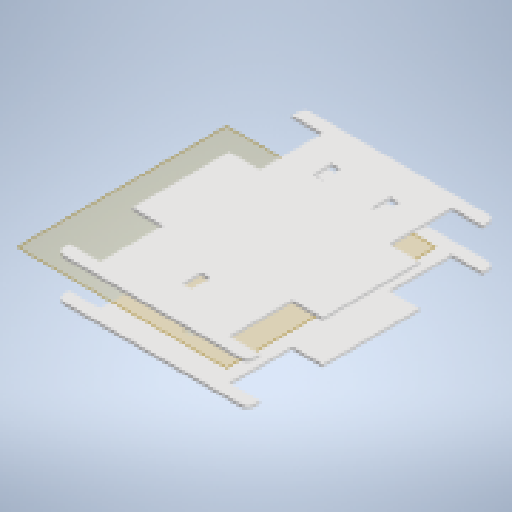
# Autodesk Inventor part: base
Saved by Autodesk Inventor 2025.2 (Build 292293000, 293)
## iProperties
Created: 2026-05-19
Part Number: base
Material: Generic
Document SubType Name: Modeling
Designer: joaoc
Density: 1 g/cm^3
Appearance: Default
Author: joaoc
Autodesk Inventor part; units mm, degrees
ref_plane "YZ Plane" through (0, 0, 0) normal (1, 0, 0) x (0, 1, 0)
ref_plane "XZ Plane" through (0, 0, 0) normal (0, 1, 0) x (-1, 0, 0)
ref_plane "XY Plane" through (0, 0, 0) normal (0, 0, 1) x (1, 0, 0)
sketch "Sketch1" plane through (0, 0, 0) normal (0, 1, 0) x (-1, 0, 0)
  line L0 (-400, 0) -> (-400, 13.2)
  arc A0 (-386.8, 26.4) -> (-400, 13.2) centre (-386.8, 13.2) ccw
  line L1 (-386.8, 26.4) -> (-13.2, 26.4)
  arc A1 (0, 13.2) -> (-13.2, 26.4) centre (-13.2, 13.2) ccw
  line L2 (0, 13.2) -> (0, 0)
  line L3 (-400, -335.4) -> (-335.4, -335.4)
  line L4 (-335.4, -335.4) -> (-335.4, -467.2)
  line L5 (-335.4, -467.2) -> (-400, -467.2)
  line L6 (-400, -131.8) -> (-335.4, -131.8)
  line L7 (-335.4, -131.8) -> (-335.4, 0)
  line L8 (-335.4, 0) -> (-400, 0)
  line L9 (0, -335.4) -> (-64.6, -335.4)
  line L10 (-64.6, -335.4) -> (-64.6, -467.2)
  line L11 (-64.6, -467.2) -> (0, -467.2)
  line L12 (0, -131.8) -> (-64.6, -131.8)
  line L13 (-64.6, -131.8) -> (-64.6, 0)
  line L14 (-64.6, 0) -> (0, 0)
  line L15 (-400, -335.4) -> (-400, -131.8)
  line L16 (0, -467.2) -> (0, -480.4)
  arc A2 (-13.2, -493.6) -> (0, -480.4) centre (-13.2, -480.4) ccw
  line L17 (-13.2, -493.6) -> (-386.8, -493.6)
  arc A3 (-400, -480.4) -> (-386.8, -493.6) centre (-386.8, -480.4) ccw
  line L18 (-400, -480.4) -> (-400, -467.2)
  line L19 (0, -131.8) -> (0, -335.4)
  line L20 (-210, -45.9) -> (-190, -45.9)
  line L21 (-190, -45.9) -> (-190, -85.9)
  line L22 (-190, -85.9) -> (-210, -85.9)
  line L23 (-210, -85.9) -> (-210, -45.9)
  line L24 (-271.3, -381.3) -> (-251.3, -381.3)
  line L25 (-251.3, -381.3) -> (-251.3, -421.3)
  line L26 (-251.3, -421.3) -> (-271.3, -421.3)
  line L27 (-271.3, -421.3) -> (-271.3, -381.3)
  line L28 (-148.7, -381.3) -> (-128.7, -381.3)
  line L29 (-128.7, -381.3) -> (-128.7, -421.3)
  line L30 (-128.7, -421.3) -> (-148.7, -421.3)
  line L31 (-148.7, -421.3) -> (-148.7, -381.3)
  point P0 (-400, -335.4)
  point P1 (-400, -467.2)
  point P2 (-400, -480.4)
  point P3 (-13.2, -493.6)
  point P4 (0, -480.4)
  point P5 (-13.2, 26.4)
  point P6 (-386.8, 26.4)
  point P7 (-400, 13.2)
  constraints: 64 end point, 8 point on circle, 4 centre point
extrude "Extrusion1" add sketch "Sketch1" along normal blind 6
ref_plane "Work Plane1" through (0, 85, 0) normal (0, 1, 0) x (1, 0, 0)
sketch "Sketch2" plane through (0, 85, 0) normal (0, 1, 0) x (1, 0, 0)
  line L0 (400, 0) -> (400, -13.2)
  arc A0 (386.8, -26.4) -> (400, -13.2) centre (386.8, -13.2) ccw
  line L1 (386.8, -26.4) -> (13.2, -26.4)
  arc A1 (0, -13.2) -> (13.2, -26.4) centre (13.2, -13.2) ccw
  line L2 (0, -13.2) -> (0, 0)
  line L3 (400, 335.4) -> (400, 131.8)
  line L4 (0, 467.2) -> (0, 480.4)
  arc A2 (13.2, 493.6) -> (0, 480.4) centre (13.2, 480.4) ccw
  line L5 (13.2, 493.6) -> (386.8, 493.6)
  arc A3 (400, 480.4) -> (386.8, 493.6) centre (386.8, 480.4) ccw
  line L6 (400, 480.4) -> (400, 467.2)
  line L7 (0, 131.8) -> (0, 335.4)
  line L8 (210, 45.9) -> (190, 45.9)
  line L9 (190, 45.9) -> (190, 85.9)
  line L10 (190, 85.9) -> (210, 85.9)
  line L11 (210, 85.9) -> (210, 45.9)
  line L12 (271.3, 381.3) -> (251.3, 381.3)
  line L13 (251.3, 381.3) -> (251.3, 421.3)
  line L14 (251.3, 421.3) -> (271.3, 421.3)
  line L15 (271.3, 421.3) -> (271.3, 381.3)
  line L16 (148.7, 381.3) -> (128.7, 381.3)
  line L17 (128.7, 381.3) -> (128.7, 421.3)
  line L18 (128.7, 421.3) -> (148.7, 421.3)
  line L19 (148.7, 421.3) -> (148.7, 381.3)
  line L20 (400, 131.8) -> (400, 0)
  line L21 (0, 0) -> (0, 131.8)
  line L22 (0, 335.4) -> (0, 467.2)
  line L23 (400, 335.4) -> (400, 467.2)
  point P0 (0, -13.2)
  constraints: 48 end point, 8 point on circle, 4 centre point, 2 vertical, 1 collinear, 1 parallel
extrude "Extrusion2" add sketch "Sketch2" along normal blind 6
body "Solid1"
